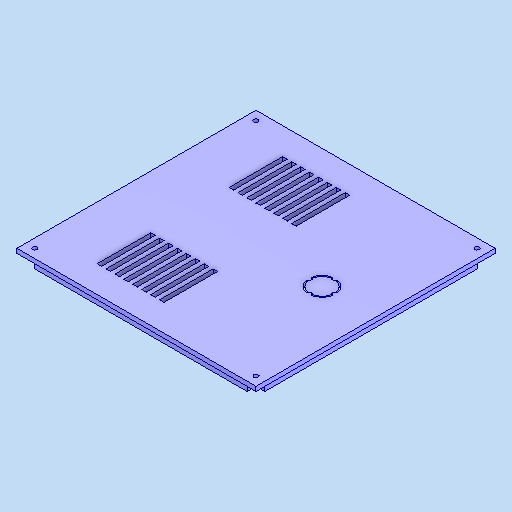
# Autodesk Inventor part: Techo_Superior
Saved by Autodesk Inventor 2027 (Build 310192000, 192)
## iProperties
Created: 2026-11-02
Part Number: Techo_Superior
Material: Plástico PAEK
Document SubType Name: Modeling
Designer: alex
Density: 1.32 g/cm^3
Appearance: Suave - Blanco
Author: alex
Autodesk Inventor part; units mm, degrees
ref_plane "YZ Plane" through (0, 0, 0) normal (1, 0, 0) x (0, 1, 0)
ref_plane "XZ Plane" through (0, 0, 0) normal (0, 1, 0) x (-1, 0, 0)
ref_plane "XY Plane" through (0, 0, 0) normal (0, 0, 1) x (1, 0, 0)
sketch "Boceto1" plane through (0, 0, 0) normal (0, 1, 0) x (-1, 0, 0)
  line L0 (120.1133, 140.628) -> (-147.8867, 140.628)
  line L1 (-147.8867, 140.628) -> (-147.8867, -127.372)
  line L2 (-147.8867, -127.372) -> (120.1133, -127.372)
  line L3 (120.1133, -127.372) -> (120.1133, 140.628)
  line L4 (115.1133, 135.628) -> (-142.8867, 135.628)
  line L5 (-142.8867, 135.628) -> (-142.8867, -122.372)
  line L6 (-142.8867, -122.372) -> (115.1133, -122.372)
  line L7 (115.1133, -122.372) -> (115.1133, 135.628)
  line L8 (120.1133, 140.628) -> (110.1133, 140.628)
  line L9 (110.1133, 140.628) -> (110.1133, 130.628)
  line L10 (110.1133, 130.628) -> (120.1133, 130.628)
  line L11 (120.1133, 130.628) -> (120.1133, 140.628)
  line L12 (-147.8867, 140.628) -> (-137.8867, 140.628)
  line L13 (-137.8867, 140.628) -> (-137.8867, 130.628)
  line L14 (-137.8867, 130.628) -> (-147.8867, 130.628)
  line L15 (-147.8867, 130.628) -> (-147.8867, 140.628)
  line L16 (-147.8867, -127.372) -> (-137.8867, -127.372)
  line L17 (-137.8867, -127.372) -> (-137.8867, -117.372)
  line L18 (-137.8867, -117.372) -> (-147.8867, -117.372)
  line L19 (-147.8867, -117.372) -> (-147.8867, -127.372)
  line L20 (120.1133, -127.372) -> (110.1133, -127.372)
  line L21 (110.1133, -127.372) -> (110.1133, -117.372)
  line L22 (110.1133, -117.372) -> (120.1133, -117.372)
  line L23 (120.1133, -117.372) -> (120.1133, -127.372)
  line L24 (120.1133, 140.628) -> (105.1133, 140.628)
  line L25 (105.1133, 140.628) -> (105.1133, 125.628)
  line L26 (105.1133, 125.628) -> (120.1133, 125.628)
  line L27 (120.1133, 125.628) -> (120.1133, 140.628)
  line L28 (120.1133, -127.372) -> (105.1133, -127.372)
  line L29 (105.1133, -127.372) -> (105.1133, -112.372)
  line L30 (105.1133, -112.372) -> (120.1133, -112.372)
  line L31 (120.1133, -112.372) -> (120.1133, -127.372)
  line L32 (-147.8867, -127.372) -> (-132.8867, -127.372)
  line L33 (-132.8867, -127.372) -> (-132.8867, -112.372)
  line L34 (-132.8867, -112.372) -> (-147.8867, -112.372)
  line L35 (-147.8867, -112.372) -> (-147.8867, -127.372)
  line L36 (-147.8867, 140.628) -> (-132.8867, 140.628)
  line L37 (-132.8867, 140.628) -> (-132.8867, 125.628)
  line L38 (-132.8867, 125.628) -> (-147.8867, 125.628)
  line L39 (-147.8867, 125.628) -> (-147.8867, 140.628)
  circle A0 centre (-137.8867, 130.628) radius 2.5
  circle A1 centre (-137.8867, -117.372) radius 2.5
  circle A2 centre (110.1133, -117.372) radius 2.5
  circle A3 centre (110.1133, 130.628) radius 2.5
  line L40 (-132.8867, 135.628) -> (105.1133, 135.628)
  line L41 (105.1133, 135.628) -> (105.1133, 130.628)
  line L42 (105.1133, 130.628) -> (-132.8867, 130.628)
  line L43 (-132.8867, 130.628) -> (-132.8867, 135.628)
  line L44 (-142.8867, 125.628) -> (-137.8867, 125.628)
  line L45 (-137.8867, 125.628) -> (-137.8867, -112.372)
  line L46 (-137.8867, -112.372) -> (-142.8867, -112.372)
  line L47 (-142.8867, -112.372) -> (-142.8867, 125.628)
  line L48 (-132.8867, -122.372) -> (105.1133, -122.372)
  line L49 (105.1133, -122.372) -> (105.1133, -117.372)
  line L50 (105.1133, -117.372) -> (-132.8867, -117.372)
  line L51 (-132.8867, -117.372) -> (-132.8867, -122.372)
  line L52 (110.1133, -112.372) -> (115.1133, -112.372)
  line L53 (115.1133, -112.372) -> (115.1133, 125.628)
  line L54 (115.1133, 125.628) -> (110.1133, 125.628)
  line L55 (110.1133, 125.628) -> (110.1133, -112.372)
  circle A4 centre (-87.8867, 6.628) radius 15
  line L56 (60.1133, 110.628) -> (55.1133, 110.628)
  line L57 (55.1133, 110.628) -> (55.1133, 50.628)
  line L58 (55.1133, 50.628) -> (60.1133, 50.628)
  line L59 (60.1133, 50.628) -> (60.1133, 110.628)
  line L60 (60.1133, -37.372) -> (55.1133, -37.372)
  line L61 (55.1133, -37.372) -> (55.1133, -97.372)
  line L62 (55.1133, -97.372) -> (60.1133, -97.372)
  line L63 (60.1133, -97.372) -> (60.1133, -37.372)
  line L64 (45.1133, 50.628) -> (50.1133, 50.628)
  line L65 (50.1133, 50.628) -> (50.1133, 110.628)
  line L66 (45.1133, 110.628) -> (45.1133, 50.628)
  line L67 (50.1133, 110.628) -> (45.1133, 110.628)
  line L68 (50.1133, -37.372) -> (45.1133, -37.372)
  line L69 (45.1133, -37.372) -> (45.1133, -97.372)
  line L70 (50.1133, -97.372) -> (50.1133, -37.372)
  line L71 (45.1133, -97.372) -> (50.1133, -97.372)
  line L72 (35.1133, 50.628) -> (40.1133, 50.628)
  line L73 (40.1133, 50.628) -> (40.1133, 110.628)
  line L74 (35.1133, 110.628) -> (35.1133, 50.628)
  line L75 (40.1133, 110.628) -> (35.1133, 110.628)
  line L76 (40.1133, -37.372) -> (35.1133, -37.372)
  line L77 (35.1133, -37.372) -> (35.1133, -97.372)
  line L78 (40.1133, -97.372) -> (40.1133, -37.372)
  line L79 (35.1133, -97.372) -> (40.1133, -97.372)
  line L80 (25.1133, 50.628) -> (30.1133, 50.628)
  line L81 (30.1133, 50.628) -> (30.1133, 110.628)
  line L82 (25.1133, 110.628) -> (25.1133, 50.628)
  line L83 (30.1133, 110.628) -> (25.1133, 110.628)
  line L84 (30.1133, -37.372) -> (25.1133, -37.372)
  line L85 (25.1133, -37.372) -> (25.1133, -97.372)
  line L86 (30.1133, -97.372) -> (30.1133, -37.372)
  line L87 (25.1133, -97.372) -> (30.1133, -97.372)
  line L88 (15.1133, 50.628) -> (20.1133, 50.628)
  line L89 (20.1133, 50.628) -> (20.1133, 110.628)
  line L90 (15.1133, 110.628) -> (15.1133, 50.628)
  line L91 (20.1133, 110.628) -> (15.1133, 110.628)
  line L92 (20.1133, -37.372) -> (15.1133, -37.372)
  line L93 (15.1133, -37.372) -> (15.1133, -97.372)
  line L94 (20.1133, -97.372) -> (20.1133, -37.372)
  line L95 (15.1133, -97.372) -> (20.1133, -97.372)
  line L96 (5.1133, 50.628) -> (10.1133, 50.628)
  line L97 (10.1133, 50.628) -> (10.1133, 110.628)
  line L98 (5.1133, 110.628) -> (5.1133, 50.628)
  line L99 (10.1133, 110.628) -> (5.1133, 110.628)
  line L100 (10.1133, -37.372) -> (5.1133, -37.372)
  line L101 (5.1133, -37.372) -> (5.1133, -97.372)
  line L102 (10.1133, -97.372) -> (10.1133, -37.372)
  line L103 (5.1133, -97.372) -> (10.1133, -97.372)
  line L104 (-4.8867, 50.628) -> (0.1133, 50.628)
  line L105 (0.1133, 50.628) -> (0.1133, 110.628)
  line L106 (-4.8867, 110.628) -> (-4.8867, 50.628)
  line L107 (0.1133, 110.628) -> (-4.8867, 110.628)
  line L108 (0.1133, -37.372) -> (-4.8867, -37.372)
  line L109 (-4.8867, -37.372) -> (-4.8867, -97.372)
  line L110 (0.1133, -97.372) -> (0.1133, -37.372)
  line L111 (-4.8867, -97.372) -> (0.1133, -97.372)
  line L112 (-14.8867, 50.628) -> (-9.8867, 50.628)
  line L113 (-9.8867, 50.628) -> (-9.8867, 110.628)
  line L114 (-14.8867, 110.628) -> (-14.8867, 50.628)
  line L115 (-9.8867, 110.628) -> (-14.8867, 110.628)
  line L116 (-9.8867, -37.372) -> (-14.8867, -37.372)
  line L117 (-14.8867, -37.372) -> (-14.8867, -97.372)
  line L118 (-9.8867, -97.372) -> (-9.8867, -37.372)
  line L119 (-14.8867, -97.372) -> (-9.8867, -97.372)
  point P0 (0, 0)
  point P1 (105.1133, 135.628)
  point P2 (-142.8867, -112.372)
  point P3 (115.1133, -112.372)
  point P4 (105.1133, -122.372)
  dimension "d0" = 268
  dimension "d1" = 268
  dimension "d2" = 5
  dimension "d3" = 5
  dimension "d4" = 5
  dimension "d5" = 5
  dimension "d6" = 10
  dimension "d7" = 10
  dimension "d8" = 10
  dimension "d9" = 10
  dimension "d10" = 10
  dimension "d11" = 10
  dimension "d12" = 10
  dimension "d13" = 10
  dimension "d14" = 15
  dimension "d15" = 15
  dimension "d16" = 15
  dimension "d17" = 15
  dimension "d18" = 15
  dimension "d19" = 15
  dimension "d20" = 15
  dimension "d21" = 15
  dimension "d22" = 5
  dimension "d23" = 5
  dimension "d24" = 5
  dimension "d25" = 5
  dimension "d26" = 30
  dimension "d27" = 60
  dimension "d28" = 134
  dimension "d29" = 5
  dimension "d30" = 60
  dimension "d31" = 30
  dimension "d32" = 60
  dimension "d33" = 5
  dimension "d34" = 60
  dimension "d35" = 60
  dimension "d36" = 30
  dimension "d39" = 10
  constraints: 240 end point, 32 parallel, 20 point on line, 17 horizontal, 16 perpendicular, 5 centre point, 4 coincident, 1 collinear, 111 other
  measures "d0" distance of L2.end L1.end
  measures "d1" distance of L1.end L0.end
  measures "d2" distance between parallel lines of L7 L3
  measures "d3" distance between parallel lines of L4 L0
  measures "d4" distance between parallel lines of L5 L1
  measures "d5" distance between parallel lines of L6 L2
  measures "d6" distance of L10.end L9.end
  measures "d7" distance of L9.end L8.end
  measures "d8" distance of L13.end L14.end
  measures "d9" distance of L12.end L13.end
  measures "d10" distance of L18.end L17.end
  measures "d11" distance of L17.end L16.end
  measures "d12" distance of L21.end L22.end
  measures "d13" distance of L20.end L21.end
  measures "d14" distance of L26.end L25.end
  measures "d15" distance of L25.end L24.end
  measures "d16" distance of L29.end L30.end
  measures "d17" distance of L28.end L29.end
  measures "d18" distance of L34.end L33.end
  measures "d19" distance of L33.end L32.end
  measures "d20" distance of L37.end L38.end
  measures "d21" distance of L36.end L37.end
  measures "d22" diameter of A0
  measures "d23" diameter of A1
  measures "d24" diameter of A2
  measures "d25" diameter of A3
  measures "d26" diameter of A4
  measures "d27" distance from line of L1 A4.centre
  measures "d28" distance from line of L0 A4.centre
  measures "d29" distance of L58.end L57.end
  measures "d30" distance of L57.end L56.end
  measures "d31" distance between parallel lines of L0 L56
  measures "d32" distance between parallel lines of L3 L59
  measures "d33" distance of L62.end L61.end
  measures "d34" distance of L61.end L60.end
  measures "d35" distance between parallel lines of L3 L63
  measures "d36" distance between parallel lines of L2 L62
  measures "d39" distance of L57.end L64.start
extrude "Extrusión1" add sketch "Boceto1" along normal blind 5 contours L3 L10 L7 L4 L9 L0 | L9 L4 L25 L0 | L3 L26 L7 L10 | L25 L4 L37 L0 | L9 A3 L10 L7 L26 L25 L4 | L4 L7 L10 A3 L9 | L3 L30 L7 L26 | L37 L4 L13 L0 | L25 L42 L37 L4 | L3 L22 L7 L30 | L7 L30 L55 L26 | L13 L4 L5 L14 L1 L0 | L37 L38 L5 L14 A0 L13 L4 | L25 L26 L55 L30 L29 L50 L33 L34 L45 L38 L37 L42 | L3 L2 L21 L6 L7 L22 | L7 L22 A2 L21 L6 L29 L30 | L13 A0 L14 L5 L4 | L7 L6 L21 A2 L22 | L14 L5 L38 L1 | L2 L29 L6 L21 | L38 L5 L34 L1 | L45 L34 L5 L38 | L2 L33 L6 L29 | L29 L6 L33 L50 | L34 L5 L18 L1 | L34 L33 L6 L17 A1 L18 L5 | L2 L17 L6 L33 | L18 L5 L6 L17 L2 L1 | L18 A1 L17 L6 L5
extrude "Extrusión2" add sketch "Boceto1" against normal blind 10 contours L25 L42 L37 L4 | L7 L30 L55 L26 | L45 L34 L5 L38 | L29 L6 L33 L50
sketch "Boceto2" plane through (0, 5, 0) normal (0, 1, 0) x (1, 0, 0)
  circle A0 centre (87.8867, -6.628) radius 15 projected
  circle A1 centre (87.8867, 8.372) radius 2.5
  circle A2 centre (72.8867, -6.628) radius 2.5
  circle A3 centre (87.8867, -21.628) radius 2.5
  circle A4 centre (102.8867, -6.628) radius 2.5
  point P0 (0, 0)
  point P1 (102.6784, -4.1367)
  point P2 (102.6784, -9.1193)
  point P3 (90.378, -21.4196)
  point P4 (85.3954, -21.4196)
  point P5 (73.095, -4.1367)
  point P6 (73.095, -9.1193)
  point P7 (85.3954, 8.1637)
  point P8 (90.378, 8.1637)
  dimension "d48" = 5
  dimension "d49" = 5
  dimension "d50" = 5
  dimension "d51" = 5
  constraints: 4 centre point, 4 point on circle
  measures "d48" diameter of A1
  measures "d49" diameter of A2
  measures "d50" diameter of A3
  measures "d51" diameter of A4
extrude "Extrusión3" add sketch "Boceto2" against normal blind 10 contours A0 A4 | A1 A0 | A0 A3 | A2 A0 picked at (102.0711, -7.1104) picked at (87.8867, 7.5232) picked at (87.8867, -20.7792) picked at (73.7355, -6.628)
sketch "Boceto3" plane through (0, 5, 0) normal (0, 1, 0) x (1, 0, 0)
  arc A0 (73.095, -9.1193) -> (85.3954, -21.4196) centre (87.8867, -6.628) ccw projected
  circle A1 centre (87.8867, -6.628) radius 13.6139
  arc A2 (85.3954, 8.1637) -> (90.378, 8.1637) centre (87.8867, 8.372) ccw projected
  arc A3 (85.9042, 6.8408) -> (89.8636, 6.8417) centre (87.8836, 8.3781) ccw
  arc A4 (73.095, -9.1193) -> (73.095, -4.1367) centre (72.8867, -6.628) ccw projected
  arc A5 (74.4171, -8.6048) -> (74.4171, -4.6511) centre (72.8867, -6.628) ccw
  arc A6 (89.8636, -20.0976) -> (85.9042, -20.0968) centre (87.8836, -21.6341) ccw
  arc A7 (102.6784, -4.1367) -> (102.6784, -9.1193) centre (102.8867, -6.628) ccw projected
  arc A8 (101.3563, -4.6511) -> (101.3563, -8.6048) centre (102.8867, -6.628) ccw
  arc A9 (74.4171, -8.6048) -> (74.4171, -4.6511) centre (72.8867, -6.628) ccw
  arc A10 (101.3563, -4.6511) -> (101.3563, -8.6048) centre (102.8867, -6.628) ccw
  arc A11 (85.9042, 6.8408) -> (89.8636, 6.8417) centre (87.8836, 8.3781) ccw
  arc A12 (89.8636, -20.0976) -> (85.9042, -20.0968) centre (87.8836, -21.6341) ccw
  circle A13 centre (72.8867, -6.628) radius 3
  circle A14 centre (87.8836, 8.3781) radius 3
  arc A15 (102.6784, -9.1193) -> (102.6784, -4.1367) centre (87.8867, -6.628) ccw projected
  circle A16 centre (102.8867, -6.628) radius 3
  circle A17 centre (87.8836, -21.6341) radius 3
  point P0 (0, 0)
  point P1 (85.3638, -20.0061)
  point P2 (90.4041, -20.0071)
  point P3 (101.2647, -9.1516)
  point P4 (101.2647, -4.1043)
  point P5 (90.4041, 6.7512)
  point P6 (85.3637, 6.7501)
  point P7 (74.5088, -4.1043)
  point P8 (74.5088, -9.1516)
  dimension "d54" = 6
  dimension "d55" = 6
  dimension "d56" = 6
  dimension "d57" = 6
  constraints: 22 point on circle, 12 centre point, 4 coincident, 3 concentric, 11 other
  measures "d54" diameter of A13
  measures "d55" diameter of A14
  measures "d56" diameter of A16
  measures "d57" diameter of A17
extrude "Extrusión4" add sketch "Boceto3" against normal blind 10 contours A1 A14 A16 A17 A13
